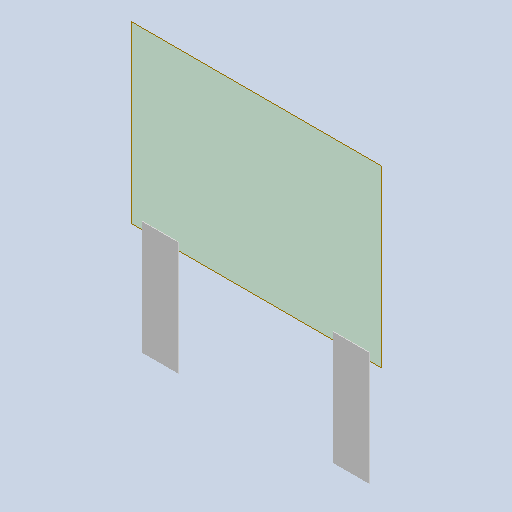
# Autodesk Inventor part: зона2
Saved by Autodesk Inventor 2024.2 (Build 282272000, 272)
## iProperties
Created: 2026-10-08
Part Number: зона2
Material: Типовые
Document SubType Name: Modeling
Designer: User
Density: 1 g/cm^3
Appearance: По умолчанию
Author: User
Autodesk Inventor part; units mm, degrees
ref_plane "YZ Plane" through (0, 0, 0) normal (1, 0, 0) x (0, 1, 0)
ref_plane "XZ Plane" through (0, 0, 0) normal (0, 1, 0) x (-1, 0, 0)
ref_plane "XY Plane" through (0, 0, 0) normal (0, 0, 1) x (1, 0, 0)
ref_plane "РабПлоскость1" through (0, 0, -2) normal (0, 0, -1) x (-1, 0, 0)
sketch "Эскиз1" plane through (0, 0, -2) normal (0, 0, -1) x (-1, 0, 0)
  line L0 (-250, -175) -> (250, -175)
  line L1 (250, -175) -> (250, -425)
  line L2 (250, -425) -> (-250, -425)
  line L3 (-250, -425) -> (-250, -175)
  line L4 (-170, -175) -> (-170, -425)
  line L5 (170, -175) -> (170, -425)
  point P0 (0, 0)
  dimension "d0" = 175
  dimension "d1" = 250
  dimension "d2" = 250
  dimension "d3" = 250
  dimension "d4" = 80
  dimension "d5" = 80
  constraints: 12 end point, 4 point on line, 3 perpendicular, 2 parallel, 1 horizontal
  measures "d0" distance from line of L0 point (0, 0)
  measures "d1" distance from line of point (0, 0) L1
  measures "d2" distance from line of L3 point (0, 0)
  measures "d3" distance between parallel lines of L0 L2
  measures "d4" distance between parallel lines of L3 L4
  measures "d5" distance between parallel lines of L1 L5
extrude "Выдавливание1" add sketch "Эскиз1" against normal blind 2 contours L0 L4 L2 L3 | L0 L1 L2 L5
